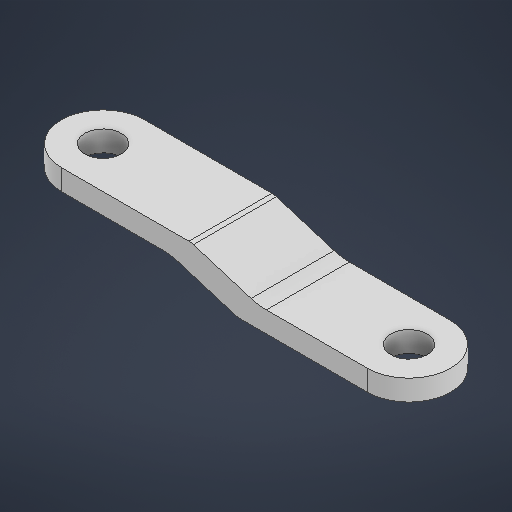
# Autodesk Inventor part: Part2
Saved by Autodesk Inventor 2025.4 (Build 294407000, 407)
## iProperties
Created: 2026-06-25
Part Number: Part2
Material: Generic
Document SubType Name: Modeling
Designer: VuQuan
Density: 1 g/cm^3
Appearance: Default
Author: VuQuan
Autodesk Inventor part; units mm, degrees
ref_plane "YZ Plane" through (0, 0, 0) normal (1, 0, 0) x (0, 1, 0)
ref_plane "XZ Plane" through (0, 0, 0) normal (0, 1, 0) x (-1, 0, 0)
ref_plane "XY Plane" through (0, 0, 0) normal (0, 0, 1) x (1, 0, 0)
sketch "Sketch1" plane through (0, 0, 0) normal (0, 0, 1) x (1, 0, 0)
  line L0 (0, 0) -> (0, 8)
  line L1 (0, 8) -> (65.1066, 8)
  line L2 (66.8723, 7.7343) -> (89.1144, 0.8856)
  line L3 (95, 0) -> (150, 0)
  line L4 (150, 0) -> (150, -8)
  line L5 (150, -8) -> (84.8934, -8)
  line L6 (83.1277, -7.7343) -> (60.8856, -0.8856)
  line L7 (55, 0) -> (0, 0)
  arc A0 (83.1277, -7.7343) -> (84.8934, -8) centre (84.8934, -2) ccw
  arc A1 (66.8723, 7.7343) -> (65.1066, 8) centre (65.1066, 2) ccw
  arc A2 (89.1144, 0.8856) -> (95, 0) centre (95, 20) ccw
  arc A3 (60.8856, -0.8856) -> (55, 0) centre (55, -20) ccw
  point P0 (58.0094, 0)
  dimension "d0" = 150
  dimension "d1" = 8
  dimension "d2" = 16
  dimension "d3" = 10
  dimension "d4" = 6
  dimension "d5" = 20
  dimension "d6" = 20
  dimension "d7" = 40
  constraints: 16 end point, 8 point on circle, 8 tangent, 6 point on line, 4 centre point, 3 parallel, 3 perpendicular, 1 coincident, 1 equal radius, 1 vertical
  measures "d0" distance between parallel lines of L4 L0
  measures "d1" distance between parallel lines of L5 L7
  measures "d2" distance between parallel lines of L5 L1
  measures "d3" distance between parallel lines of L2 L6
  measures "d4" radius of A0
  measures "d5" radius of A2
  measures "d6" radius of A3
  measures "d7" distance of L3.start L7.start
extrude "Extrusion1" add sketch "Sketch1" along normal blind 32
fillet "Fillet1" radius 16 4 edges at (150, -4, 32) (150, -4, 0) (0, 4, 32) (0, 4, 0)
sketch "Sketch2" plane through (65.1066, 8, 32) normal (0, 1, 0) x (1, 0, 0)
  arc A0 (-49.1066, 32) -> (-49.1066, 0) centre (-49.1066, 16) ccw projected
  point P0 (-65.1066, 32)
  constraints: 1 coincident
hole "Hole1" at (16, 8, 16) direction (0, -1, 0) diameter 14 end through all
sketch "Sketch3" plane through (95, 0, 32) normal (0, 1, 0) x (1, 0, 0)
  arc A0 (39, 0) -> (39, 32) centre (39, 16) ccw projected
  point P0 (-95, 32)
  constraints: 1 coincident
hole "Hole2" at (134, 0, 16) direction (0, -1, 0) diameter 14 end through all
body "Solid1"
